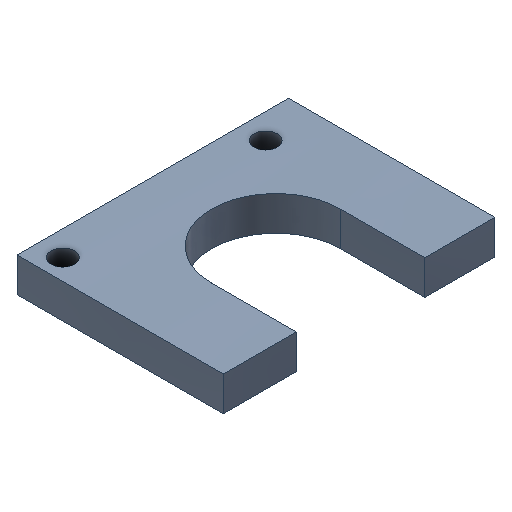
# Autodesk Inventor part: OT2-Pipette V0.6 - pipette seat
Saved by Autodesk Inventor 2025.5 (Build 295498000, 498)
## iProperties
Created: 2026-11-20
Part Number: OT2-Pipette V0.6 - pipette seat
Material: Generisch
Description: printed pipette seat: fork under the body bottom, 2 M3 screws into the wall (takes plunger and eject forces)
Document SubType Name: Modeling
Designer: benir
Density: 1 g/cm^3
Appearance: Light Steel Blue
Author: benir
Autodesk Inventor part; units mm, degrees
ref_plane "YZ Plane" through (0, 0, 0) normal (1, 0, 0) x (0, 1, 0)
ref_plane "y=body_bottom - seat_t" through (0, -71, 0) normal (0, 1, 0) x (-1, 0, 0)
sketch "seat plate" plane through (0, -71, 0) normal (0, 1, 0) x (-1, 0, 0)
  line L0 (9.5, -23) -> (-20.5, -23)
  line L1 (-20.5, -23) -> (-20.5, 16.5)
  line L2 (-20.5, 16.5) -> (9.5, 16.5)
  line L3 (9.5, 16.5) -> (9.5, -23)
  line L4 (0, -30.9) -> (0, 24.4) projected
  line L5 (15.5, 0) -> (-26.5, 0) projected
  point P0 (0, 0)
  dimension "d3" = 30
  dimension "d4" = 39.5
  dimension "d5" = 9.5
  dimension "d6" = 23
  constraints: 8 end point, 2 parallel, 1 horizontal, 1 perpendicular
  measures "d3" distance of L0.start L0.end
  measures "d4" distance of L2.end L0.start
  measures "d5" horizontal distance of point (0, 0) L2.end
  measures "d6" vertical distance of point (0, 0) L0.start
extrude "Extrusion2" add sketch "seat plate" along normal blind 5
ref_plane "y=body_bottom - seat_t - cut_over" through (0, -72, 0) normal (0, 1, 0) x (-1, 0, 0)
sketch "collar hole" plane through (0, -72, 0) normal (0, 1, 0) x (-1, 0, 0)
  circle A0 centre (-8.2, -3.46) radius 9.35
  point P0 (0, 0)
  dimension "d10" = 3.46
  dimension "d11" = 8.2
  dimension "d12" = 18.7
  constraints: 1 centre point
  measures "d10" vertical distance of point (0, 0) A0.centre
  measures "d11" horizontal distance of point (0, 0) A0.centre
  measures "d12" diameter of A0
extrude "Extrusion3" cut sketch "collar hole" along normal blind 7
sketch "fork opening" plane through (0, -72, 0) normal (0, 1, 0) x (-1, 0, 0)
  line L0 (-8.2, -12.81) -> (-21.5, -12.81)
  line L1 (-21.5, -12.81) -> (-21.5, 5.89)
  line L2 (-21.5, 5.89) -> (-8.2, 5.89)
  line L3 (-8.2, 5.89) -> (-8.2, -12.81)
  line L4 (0, -30.9) -> (0, 24.4) projected
  line L5 (15.7, 0) -> (-27.7, 0) projected
  point P0 (0, 0)
  dimension "d15" = 13.3
  dimension "d16" = 18.7
  dimension "d17" = 8.2
  dimension "d18" = 12.81
  constraints: 8 end point, 2 parallel, 1 horizontal, 1 perpendicular
  measures "d15" distance of L0.start L0.end
  measures "d16" distance of L2.end L0.start
  measures "d17" horizontal distance of point (0, 0) L2.end
  measures "d18" vertical distance of point (0, 0) L0.start
extrude "fork opening toward +x" cut sketch "fork opening" along normal blind 7
sketch "screw holes" plane through (0, -72, 0) normal (0, 1, 0) x (-1, 0, 0)
  circle A0 centre (5.85, 13.5) radius 1.7
  circle A1 centre (5.85, -16) radius 1.7
  point P0 (0, 0)
  dimension "d21" = 13.5
  dimension "d22" = 5.85
  dimension "d23" = 3.4
  dimension "d24" = 16
  dimension "d25" = 5.85
  dimension "d26" = 3.4
  constraints: 2 centre point
  measures "d21" vertical distance of point (0, 0) A0.centre
  measures "d22" horizontal distance of point (0, 0) A0.centre
  measures "d23" diameter of A0
  measures "d24" vertical distance of point (0, 0) A1.centre
  measures "d25" horizontal distance of point (0, 0) A1.centre
  measures "d26" diameter of A1
extrude "2 x M3 clearance holes" cut sketch "screw holes" along normal blind 7
equation "\"d3\" = seat_x1 - mount_x"
equation "\"d4\" = seat_z1 - seat_z0"
equation "\"d5\" = -mount_x"
equation "\"d6\" = -seat_z0"
equation "\"d7\" = seat_t"
equation "\"d10\" = -pip_z"
equation "\"d11\" = pip_x"
equation "\"d12\" = seat_hole_d"
equation "\"d13\" = seat_t + 2 * cut_over"
equation "\"d15\" = cut_over + seat_x1 - pip_x"
equation "\"d16\" = seat_hole_d + 0 * pip_z"
equation "\"d17\" = pip_x"
equation "\"d18\" = 0.5 * seat_hole_d - pip_z"
equation "\"d19\" = seat_t + 2 * cut_over"
equation "\"d21\" = seat_screw_z1"
equation "\"d22\" = -seat_screw_x"
equation "\"d23\" = seat_screw_d"
equation "\"d24\" = -seat_screw_z2"
equation "\"d25\" = -seat_screw_x"
equation "\"d26\" = seat_screw_d"
equation "\"d27\" = seat_t + 2 * cut_over"
equation "\"seat_x1\" = 20.5"
equation "\"mount_x\" = -9.5"
equation "\"seat_z1\" = 16.5"
equation "\"seat_z0\" = -23"
equation "\"seat_t\" = 5"
equation "\"seat_hole_d\" = 18.7"
equation "\"cut_over\" = 1"
equation "\"pip_x\" = 8.2"
equation "\"pip_z\" = -3.46"
equation "\"seat_screw_d\" = 3.4"
equation "\"seat_screw_z1\" = 13.5"
equation "\"seat_screw_x\" = -5.85"
equation "\"seat_screw_z2\" = -16"
body "Solid2"
